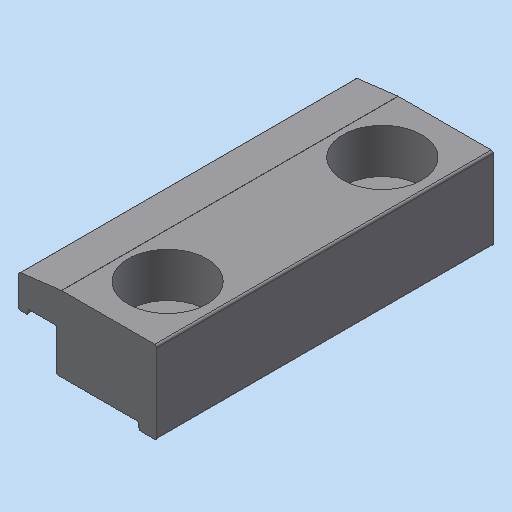
# Autodesk Inventor part: MM0868AN100_G80_504
Saved by Autodesk Inventor 2023.3 (Build 273359000, 359)
## iProperties
RuleStatus: InUse
Created: 2020-12-04
Part Number: MM0868AN100_G80_504
Material: Generisch
Description: =<RBPARTNOTITLE2>
Document SubType Name: Modeling
Designer: RUD
Mass: 58.3819 g
Surface Area: 36.9455 cm^2
Volume: 6.63431 cm^3
Density: 8.8 g/cm^3
Appearance: Vorgabe
Vendor: Bosch Rexroth
AnP_Kategorie: 2
AnP_Material: =<Material>
AnP_TemplVers: 20200821
RBDOCUMENTTYPE: DRF
RBDOCUMENTVERSION: 00
RBDRAWINGMAINSCALE: 1:1
RBDRAWINGMISSINGSPEC: --
RBDRAWINGVOLUME: --
RBDSV1: 0850
RBGBEDGESIN1: +0,5
RBGBEDGESIN2: +0,2
RBGBEDGESOUT1: -0,3
RBGBEDGESOUT2: -0,1
RBMATERIAL: --
RBMATMEETS: --
RBMATNO: =<Part Number>
RBPARTMADEOF: R0375 510 23
RBPARTNO: SIEHE MNR
RBPARTNOTITLE1: Clamping item
RBPARTNOTITLE2: Spannstück
RBPARTSAFETYINDICATOR: --
RBSURFACE: --
RBSURFACE2: --
RBZEDGESNORM: ISO13715:2002-06
RBZGENDIMCLASS: m
RBZGENDIMNORM: ISO 2768-1:1989-11
RBZGENGEOCLASS: H
RBZGENGEONORM: ISO 2768-2:1989-11
RBZSURFACENORM: ISO13D2:2002-02
RBZTOLERANCENORM: ISO 14405-1:2010-12
Author: RUD
Keywords: =<RBPARTMADEOF>
Comments: =<RBSURFACE2>
Revision Number: 01
Autodesk Inventor part; units mm, degrees
ref_plane "YZ Plane" through (0, 0, 0) normal (1, 0, 0) x (0, 1, 0)
ref_plane "XZ Plane" through (0, 0, 0) normal (0, 1, 0) x (-1, 0, 0)
ref_plane "XY Plane" through (0, 0, 0) normal (0, 0, 1) x (1, 0, 0)
sketch "Skizze1" plane through (0, 0, 0) normal (0, 0, 1) x (1, 0, 0)
  line L0 (0, 13.8) -> (0, -2.3) projected
  line L1 (-23.16, 0) -> (3.86, 0) projected
  line L2 (0, 11.5) -> (0, 0)
  line L3 (0, 0) -> (-2.5, 0)
  line L4 (-2.5, 0) -> (-2.5, 1)
  line L5 (-2.5, 1) -> (-14, 1)
  line L6 (-14, 1) -> (-14, 6.9)
  line L7 (-14, 6.9) -> (-18, 6.9)
  line L8 (-18, 6.9) -> (-18, 6.2)
  line L9 (-18, 6.2) -> (-19.3, 6.2)
  line L10 (-19.3, 6.2) -> (-19.3, 10.7633)
  line L11 (-19.3, 10.7633) -> (-13.3, 11.5)
  line L12 (-13.3, 11.5) -> (0, 11.5)
  point P0 (0, 0)
  dimension "d0" = 2.5
  dimension "d1" = 1
  dimension "d2" = 14
  dimension "d3" = 4
  dimension "d4" = 1.3
  dimension "d5" = 0.7
  dimension "d6" = 6.9
  dimension "d7" = 11.5
  dimension "d8" = 7
  dimension "d9" = 6
  constraints: 22 end point, 7 perpendicular, 2 collinear, 2 vertical, 1 parallel
  measures "d0" distance between parallel lines of L0 L4
  measures "d1" distance between parallel lines of L1 L5
  measures "d2" distance between parallel lines of L0 L6
  measures "d3" distance between parallel lines of L6 L8
  measures "d4" distance between parallel lines of L10 L8
  measures "d5" distance between parallel lines of L9 L7
  measures "d6" distance between parallel lines of L1 L7
  measures "d7" distance between parallel lines of L1 L12
  measures "d8" angle of L12 L11
  measures "d9" horizontal distance of L10.end L11.end
extrude "Extrusion1" add sketch "Skizze1" against normal blind 47
sketch "Skizze2" plane through (-13.3, 11.5, 0) normal (0, 1, 0) x (1, 0, 0)
  line L0 (13.3, 56.4) -> (13.3, -9.4) projected
  line L1 (17.16, 0) -> (-9.86, 0) projected
  line L2 (6.3, 8.5) -> (6.3, 38.5)
  dimension "d12" = 8.5
  dimension "d13" = 7
  dimension "d23" = 30
  constraints: 2 end point, 1 coincident, 1 vertical
  measures "d12" distance from line of L2.start L1
  measures "d13" distance from line of L2.start L0
  measures "d23" distance of L2.start L2.end
hole "Bohrung1" at (-7, 11.5, -8.5) at (-7, 11.5, -38.5) direction (0, -1, 0) diameter 6.6 end through all counterbore diameter 11 counterbore depth 6.2
fillet "Rundung1" radius 0.2 2 edges at (-18, 6.9, -23.5) (-18, 6.2, -23.5)
fillet "Rundung2" radius 0.3 8 edges at (-19.3, 6.2, -23.5) (-19.3, 10.7633, -23.5) (-13.3, 11.5, -23.5) (-14, 1, -23.5) (-2.5, 1, -23.5) (-2.5, 0, -23.5) (0, 0, -23.5) (0, 11.5, -23.5)
